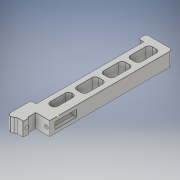
# Autodesk Inventor part: Holder
Saved by Autodesk Inventor 2019 (Build 230136000, 136)
## iProperties
Created: 2021-01-03
Part Number: Holder
Material: Generic
Document SubType Name: Modeling
Designer: Keith
Density: 1 g/cm^3
Appearance: Default
Author: Keith
## iProperties of the stored document Holder_3DPrint.ipt
Created: 2021-01-03
Part Number: Holder_3DPrint
Material: Generic
Document SubType Name: Modeling
Designer: Keith
Density: 1 g/cm^3
Appearance: Default
Author: Keith
Autodesk Inventor part; units mm, degrees
ref_plane "YZ Plane" through (0, 0, 0) normal (1, 0, 0) x (0, 1, 0)
sketch "Sketch1" plane through (0, 0, 0) normal (0, 1, 0) x (-1, 0, 0)
  line L0 (0, 0) -> (20, 0)
  line L1 (20, 0) -> (20, -100)
  line L2 (20, -100) -> (0, -100)
  line L3 (0, -100) -> (0, 0)
  line L4 (25, -100) -> (-5, -100)
  line L5 (-5, -100) -> (-5, -107.5)
  line L6 (-5, -107.5) -> (25, -107.5)
  line L7 (25, -107.5) -> (25, -100)
  line L8 (30, 0) -> (0, 0)
  line L9 (0, 0) -> (0, 7.5)
  line L10 (0, 7.5) -> (30, 7.5)
  line L11 (30, 7.5) -> (30, 0)
  line L12 (0, 7.5) -> (6, 7.5)
  line L13 (6, 7.5) -> (6, 13.5)
  line L14 (6, 13.5) -> (0, 13.5)
  line L15 (0, 13.5) -> (0, 7.5)
  dimension "d0" = 20
  dimension "d1" = 100
  dimension "d2" = 7.5
  dimension "d3" = 30
  dimension "d4" = 5
  dimension "d5" = 7.5
  dimension "d6" = 0
  dimension "d7" = 7.5
  dimension "d8" = 10
  dimension "d9" = 6
  dimension "d10" = 6
  constraints: 32 end point, 8 parallel, 4 horizontal, 4 perpendicular, 1 point on line
  measures "d0" distance of L1.end L2.end
  measures "d1" distance of L0.end L1.end
  measures "d2" distance of L6.end L4.start
  measures "d3" distance of L5.end L6.end
  measures "d4" distance between parallel lines of L7 L1
  measures "d5" distance of L8.end L9.end
  measures "d6" distance between parallel lines of L3 L9
  measures "d7" distance between parallel lines of L0 L10
  measures "d8" distance between parallel lines of L1 L11
  measures "d9" distance of L14.end L13.end
  measures "d10" distance of L13.end L12.end
extrude "Extrusion1" add sketch "Sketch1" along normal blind 13
ref_plane "Work Plane1" through (0, 6.5, 0) normal (0, 1, 0) x (1, 0, 0)
sketch "Sketch2" plane through (0, 13, 0) normal (0, 1, 0) x (1, 0, 0)
  line L0 (-25, 100) -> (-20, 100) projected
  line L1 (-20, 100) -> (-20, 0) projected
  line L2 (-20, 0) -> (-30, 0) projected
  line L3 (-30, 0) -> (-30, -7.5) projected
  line L4 (-30, -7.5) -> (-6, -7.5) projected
  line L5 (-6, -7.5) -> (-6, -13.5) projected
  line L6 (-6, -13.5) -> (0, -13.5) projected
  line L7 (0, -13.5) -> (0, 100) projected
  line L8 (0, 100) -> (5, 100) projected
  line L9 (5, 100) -> (5, 107.5) projected
  line L10 (5, 107.5) -> (-25, 107.5) projected
  line L11 (-25, 107.5) -> (-25, 100) projected
  line L12 (-30, -7.5) -> (-6, -7.5) projected
  line L13 (-30, -7.5) -> (-13, -7.5)
  line L14 (-13, -7.5) -> (-13, -20.25)
  line L15 (-13, -20.25) -> (-30, -20.25)
  line L16 (-30, -20.25) -> (-30, -7.5)
  line L17 (-13, -20.25) -> (-11.75, -20.25)
  line L18 (-11.75, -20.25) -> (-11.75, -14.75)
  line L19 (-11.75, -14.75) -> (-13, -14.75)
  line L20 (-13, -14.75) -> (-13, -20.25)
  line L21 (-13, -27.5) -> (7, -27.5)
  line L22 (7, -27.5) -> (7, -7.5)
  line L23 (7, -7.5) -> (-13, -7.5)
  line L24 (-13, -7.5) -> (-13, -27.5)
  point P0 (0, 0)
  point P1 (-3, -13.5)
  point P2 (-11.75, -17.5)
  point P3 (-13, -17.5)
  dimension "d14" = 1.25
  dimension "d15" = 5.5
  dimension "d17" = 20
  dimension "d18" = 20
  dimension "d19" = 0
  dimension "d20" = 10
  dimension "d21" = 10
  dimension "d22" = 0
  dimension "d23" = 0
  constraints: 24 end point, 6 parallel, 3 horizontal, 3 midpoint, 3 perpendicular
  measures "d14" distance of L19.end L18.end
  measures "d15" distance of L18.end L17.end
  measures "d17" distance of L23.end L22.end
  measures "d18" distance of L22.end L21.end
  measures "d19" distance between parallel lines of L4 L23
  measures "d20" distance from line of L22 point (-3, -13.5)
  measures "d21" distance from line of L4 point (-13, -17.5)
  measures "d22" vertical distance of point (-13, -17.5) point (-11.75, -17.5)
  measures "d23" distance between parallel lines of L24 L14
extrude "Extrusion2" add sketch "Sketch2" against normal up to surface (13 mm away) contours L4 L14 L15 L16 | L19 L18 L17 L14
sketch "Sketch3" plane through (0, 13, 0) normal (0, 1, 0) x (1, 0, 0)
  line L0 (-25, 100) -> (-20, 100) projected
  line L1 (-20, 100) -> (-20, 0) projected
  line L2 (-20, 0) -> (-30, 0) projected
  line L3 (-30, 0) -> (-30, -20.25) projected
  line L4 (-30, -20.25) -> (-11.75, -20.25) projected
  line L5 (-11.75, -20.25) -> (-11.75, -14.75) projected
  line L6 (-11.75, -14.75) -> (-13, -14.75) projected
  line L7 (-13, -14.75) -> (-13, -7.5) projected
  line L8 (-13, -7.5) -> (-6, -7.5) projected
  line L9 (-6, -7.5) -> (-6, -13.5) projected
  line L10 (-6, -13.5) -> (0, -13.5) projected
  line L11 (0, -13.5) -> (0, 100) projected
  line L12 (0, 100) -> (5, 100) projected
  line L13 (5, 100) -> (5, 107.5) projected
  line L14 (5, 107.5) -> (-25, 107.5) projected
  line L15 (-25, 107.5) -> (-25, 100) projected
  line L16 (-30, -20.25) -> (-11.75, -20.25) projected
  line L17 (-25, -20.25) -> (-25, 0)
  point P0 (0, 0)
  dimension "d31" = 0
  constraints: 2 end point, 1 midpoint, 1 perpendicular, 1 point on line
  measures "d31" distance between parallel lines of L15 L17
extrude "Extrusion3" cut sketch "Sketch3" against normal through all contours L17 L4 L3 L2
chamfer "Chamfer1" distance 0.5 angle 45 4 edges at (-11.75, 6.5, 14.75) (-6, 6.5, 13.5) (0, 6.5, 13.5) (-11.75, 6.5, 20.25)
fillet "Fillet1" radius 2 5 edges at (-25, 6.5, 0) (-25, 6.5, -100) (-25, 6.5, -107.5) (5, 6.5, -107.5) (5, 6.5, -100)
sketch "Sketch6" plane through (0, 13, 0) normal (0, 1, 0) x (1, 0, 0)
  arc A0 (3, 100) -> (5, 102) centre (3, 102) ccw projected
  line L0 (5, 102) -> (5, 105.5) projected
  arc A1 (5, 105.5) -> (3, 107.5) centre (3, 105.5) ccw projected
  line L1 (3, 107.5) -> (-23, 107.5) projected
  arc A2 (-23, 107.5) -> (-25, 105.5) centre (-23, 105.5) ccw projected
  line L2 (-25, 105.5) -> (-25, 102) projected
  arc A3 (-25, 102) -> (-23, 100) centre (-23, 102) ccw projected
  line L3 (-23, 100) -> (-20, 100) projected
  line L4 (-20, 100) -> (-20, 0) projected
  line L5 (-20, 0) -> (-23, 0) projected
  arc A4 (-23, 0) -> (-25, -2) centre (-23, -2) ccw projected
  line L6 (-25, -2) -> (-25, -20.25) projected
  line L7 (-25, -20.25) -> (-12.25, -20.25) projected
  line L8 (-11.75, -19.75) -> (-12.25, -20.25) projected
  line L9 (-11.75, -19.75) -> (-11.75, -15.25) projected
  line L10 (-12.25, -14.75) -> (-11.75, -15.25) projected
  line L11 (-12.25, -14.75) -> (-13, -14.75) projected
  line L12 (-13, -14.75) -> (-13, -7.5) projected
  line L13 (-13, -7.5) -> (-6, -7.5) projected
  line L14 (-6, -7.5) -> (-6, -13) projected
  line L15 (-5.5, -13.5) -> (-6, -13) projected
  line L16 (-5.5, -13.5) -> (-0.5, -13.5) projected
  line L17 (0, -13) -> (-0.5, -13.5) projected
  line L18 (0, -13) -> (0, 100) projected
  line L19 (0, 100) -> (3, 100) projected
  line L20 (-15, 5) -> (-5, 5)
  line L21 (-5, 5) -> (-5, 25)
  line L22 (-5, 25) -> (-15, 25)
  line L23 (-15, 25) -> (-15, 5)
  line L24 (-15, 30) -> (-5, 30)
  line L25 (-5, 30) -> (-5, 50)
  line L26 (-5, 50) -> (-15, 50)
  line L27 (-15, 50) -> (-15, 30)
  line L28 (-15, 55) -> (-5, 55)
  line L29 (-5, 55) -> (-5, 75)
  line L30 (-5, 75) -> (-15, 75)
  line L31 (-15, 75) -> (-15, 55)
  line L32 (-15, 80) -> (-5, 80)
  line L33 (-5, 80) -> (-5, 100)
  line L34 (-5, 100) -> (-15, 100)
  line L35 (-15, 100) -> (-15, 80)
  point P0 (0, 0)
  dimension "d45" = 5
  dimension "d46" = 20
  dimension "d47" = 20
  dimension "d48" = 20
  dimension "d49" = 20
  dimension "d50" = 5
  dimension "d51" = 5
  dimension "d52" = 5
  dimension "d53" = 10
  dimension "d54" = 5
  dimension "d55" = 5
  constraints: 32 end point, 8 parallel, 6 point on line, 4 horizontal, 4 perpendicular
  measures "d45" distance between parallel lines of L5 L20
  measures "d46" distance of L22.end L20.start
  measures "d47" distance of L26.end L24.start
  measures "d48" distance of L30.end L28.start
  measures "d49" distance of L34.end L32.start
  measures "d50" distance between parallel lines of L22 L24
  measures "d51" distance between parallel lines of L30 L32
  measures "d52" distance between parallel lines of L28 L26
  measures "d53" distance of L20.start L20.end
  measures "d54" distance between parallel lines of L4 L23
  measures "d55" distance between parallel lines of L18 L21
extrude "Extrusion5" cut sketch "Sketch6" against normal through all contours L23 L22 L21 L20 | L27 L26 L25 L24 | L31 L30 L29 L28 | L35 L34 L33 L32
sketch "Sketch7" plane through (3, 0, -107.5) normal (0, 0, -1) x (-1, 0, 0)
  line L0 (23, 13) -> (23, 0) projected
  line L1 (23, 0) -> (23, 13) projected
  line L2 (3, 0) -> (3, 13) projected
  line L3 (3, 13) -> (3, 0) projected
  circle A0 centre (22.5, 6.5) radius 2.075
  circle A1 centre (3.5, 6.5) radius 2.05
  point P0 (3, 0)
  dimension "d58" = 4.15
  dimension "d59" = 4.1
  dimension "d60" = 0.5
  dimension "d61" = 0.5
  constraints: 2 centre point
  measures "d58" diameter of A0
  measures "d59" diameter of A1
  measures "d60" distance from line of L2 A1.centre
  measures "d61" distance from line of L0 A0.centre
extrude "Extrusion6" cut sketch "Sketch7" against normal blind 110 contours A0 L0 | L0 A0
fillet "Fillet2" radius 3 16 edges at (-15, 6.5, -5) (-5, 6.5, -5) (-5, 6.5, -25) (-15, 6.5, -25) (-15, 6.5, -30) (-5, 6.5, -30) (-5, 6.5, -50) (-15, 6.5, -50) (-15, 6.5, -55) (-5, 6.5, -55) (-5, 6.5, -75) (-15, 6.5, -75) (-15, 6.5, -80) (-5, 6.5, -80) (-15, 6.5, -100) (-5, 6.5, -100)
sketch "Sketch9" plane through (0, 13, 0) normal (0, 1, 0) x (1, 0, 0)
  line L0 (-5, 72) -> (-5, 58) projected
  arc A0 (-8, 55) -> (-5, 58) centre (-8, 58) ccw projected
  line L1 (-8, 55) -> (-12, 55) projected
  arc A1 (-15, 58) -> (-12, 55) centre (-12, 58) ccw projected
  line L2 (-15, 58) -> (-15, 72) projected
  arc A2 (-12, 75) -> (-15, 72) centre (-12, 72) ccw projected
  line L3 (-12, 75) -> (-8, 75) projected
  arc A3 (-5, 72) -> (-8, 75) centre (-8, 72) ccw projected
  line L4 (-5, 22) -> (-5, 8) projected
  arc A4 (-8, 5) -> (-5, 8) centre (-8, 8) ccw projected
  line L5 (-8, 5) -> (-12, 5) projected
  arc A5 (-15, 8) -> (-12, 5) centre (-12, 8) ccw projected
  line L6 (-15, 8) -> (-15, 22) projected
  arc A6 (-12, 25) -> (-15, 22) centre (-12, 22) ccw projected
  line L7 (-12, 25) -> (-8, 25) projected
  arc A7 (-5, 22) -> (-8, 25) centre (-8, 22) ccw projected
  line L8 (-5, 47) -> (-5, 33) projected
  arc A8 (-8, 30) -> (-5, 33) centre (-8, 33) ccw projected
  line L9 (-8, 30) -> (-12, 30) projected
  arc A9 (-15, 33) -> (-12, 30) centre (-12, 33) ccw projected
  line L10 (-15, 33) -> (-15, 47) projected
  arc A10 (-12, 50) -> (-15, 47) centre (-12, 47) ccw projected
  line L11 (-12, 50) -> (-8, 50) projected
  arc A11 (-5, 47) -> (-8, 50) centre (-8, 47) ccw projected
  line L12 (-5, 97) -> (-5, 83) projected
  arc A12 (-8, 80) -> (-5, 83) centre (-8, 83) ccw projected
  line L13 (-8, 80) -> (-12, 80) projected
  arc A13 (-15, 83) -> (-12, 80) centre (-12, 83) ccw projected
  line L14 (-15, 83) -> (-15, 97) projected
  arc A14 (-12, 100) -> (-15, 97) centre (-12, 97) ccw projected
  line L15 (-12, 100) -> (-8, 100) projected
  arc A15 (-5, 97) -> (-8, 100) centre (-8, 97) ccw projected
  arc A16 (3, 100) -> (5, 102) centre (3, 102) ccw projected
  line L16 (5, 102) -> (5, 105.5) projected
  arc A17 (5, 105.5) -> (3, 107.5) centre (3, 105.5) ccw projected
  line L17 (3, 107.5) -> (-23, 107.5) projected
  arc A18 (-23, 107.5) -> (-25, 105.5) centre (-23, 105.5) ccw projected
  line L18 (-25, 105.5) -> (-25, 102) projected
  arc A19 (-25, 102) -> (-23, 100) centre (-23, 102) ccw projected
  line L19 (-23, 100) -> (-20, 100) projected
  line L20 (-20, 100) -> (-20, 0) projected
  line L21 (-20, 0) -> (-23, 0) projected
  arc A20 (-23, 0) -> (-25, -2) centre (-23, -2) ccw projected
  line L22 (-25, -2) -> (-25, -20.25) projected
  line L23 (-25, -20.25) -> (-12.25, -20.25) projected
  line L24 (-11.75, -19.75) -> (-12.25, -20.25) projected
  line L25 (-11.75, -19.75) -> (-11.75, -15.25) projected
  line L26 (-12.25, -14.75) -> (-11.75, -15.25) projected
  line L27 (-12.25, -14.75) -> (-13, -14.75) projected
  line L28 (-13, -14.75) -> (-13, -7.5) projected
  line L29 (-13, -7.5) -> (-6, -7.5) projected
  line L30 (-6, -7.5) -> (-6, -13) projected
  line L31 (-5.5, -13.5) -> (-6, -13) projected
  line L32 (-5.5, -13.5) -> (-0.5, -13.5) projected
  line L33 (0, -13) -> (-0.5, -13.5) projected
  line L34 (0, -13) -> (0, 100) projected
  line L35 (0, 100) -> (3, 100) projected
  line L36 (-25, -2) -> (-25, -20.25) projected
  line L37 (-25, -20.25) -> (-20, -20.25)
  line L38 (-20, -20.25) -> (-20, -22.25)
  line L39 (-20, -22.25) -> (-25, -22.25)
  line L40 (-25, -22.25) -> (-25, -20.25)
  point P0 (0, 0)
  dimension "d69" = 2
  constraints: 8 end point, 2 parallel, 1 horizontal, 1 perpendicular
  measures "d69" distance of L37.end L38.end
extrude "Extrusion8" add sketch "Sketch9" against normal up to surface (13 mm away) contours L23 L38 L39 L40
fillet "Fillet3" radius 3 3 edges at (-20, 6.5, 20.25) (-20, 6.5, 22.25) (-25, 6.5, 22.25)
sketch "Sketch4" plane through (-25, 13, 0) normal (-1, 0, 0) x (0, 0, 1)
  line L0 (19.25, -13) -> (2, -13) projected
  line L1 (2, 0) -> (19.25, 0) projected
  line L2 (14.75, -13) -> (14.75, 0) projected
  line L3 (20.25, 0) -> (20.25, -13) projected
  line L4 (19.25, 0) -> (19.25, -13) projected
  line L5 (2, -13) -> (2, 0) projected
  point P0 (0, -13)
  point P1 (17.25, -6.5)
  dimension "d32" = 6.5
  dimension "d33" = 2.5
  measures "d32" distance from line of L0 point (17.25, -6.5)
  measures "d33" distance from line of L2 point (17.25, -6.5)
hole "Hole1" at (-25, 6.5, 17.25) direction (1, 0, 0) diameter 3.4 end through all counterbore diameter 6.5 counterbore depth 3 clearance for "Socket Head Cap Screw" size "M3" standard "Ansi Metric M Profile"
sketch "Sketch10" plane through (0, 13, 0) normal (0, 1, 0) x (1, 0, 0)
  line L0 (-5, 72) -> (-5, 58) projected
  arc A0 (-8, 55) -> (-5, 58) centre (-8, 58) ccw projected
  line L1 (-8, 55) -> (-12, 55) projected
  arc A1 (-15, 58) -> (-12, 55) centre (-12, 58) ccw projected
  line L2 (-15, 58) -> (-15, 72) projected
  arc A2 (-12, 75) -> (-15, 72) centre (-12, 72) ccw projected
  line L3 (-12, 75) -> (-8, 75) projected
  arc A3 (-5, 72) -> (-8, 75) centre (-8, 72) ccw projected
  line L4 (-5, 22) -> (-5, 8) projected
  arc A4 (-8, 5) -> (-5, 8) centre (-8, 8) ccw projected
  line L5 (-8, 5) -> (-12, 5) projected
  arc A5 (-15, 8) -> (-12, 5) centre (-12, 8) ccw projected
  line L6 (-15, 8) -> (-15, 22) projected
  arc A6 (-12, 25) -> (-15, 22) centre (-12, 22) ccw projected
  line L7 (-12, 25) -> (-8, 25) projected
  arc A7 (-5, 22) -> (-8, 25) centre (-8, 22) ccw projected
  line L8 (-5, 47) -> (-5, 33) projected
  arc A8 (-8, 30) -> (-5, 33) centre (-8, 33) ccw projected
  line L9 (-8, 30) -> (-12, 30) projected
  arc A9 (-15, 33) -> (-12, 30) centre (-12, 33) ccw projected
  line L10 (-15, 33) -> (-15, 47) projected
  arc A10 (-12, 50) -> (-15, 47) centre (-12, 47) ccw projected
  line L11 (-12, 50) -> (-8, 50) projected
  arc A11 (-5, 47) -> (-8, 50) centre (-8, 47) ccw projected
  line L12 (-5, 97) -> (-5, 83) projected
  arc A12 (-8, 80) -> (-5, 83) centre (-8, 83) ccw projected
  line L13 (-8, 80) -> (-12, 80) projected
  arc A13 (-15, 83) -> (-12, 80) centre (-12, 83) ccw projected
  line L14 (-15, 83) -> (-15, 97) projected
  arc A14 (-12, 100) -> (-15, 97) centre (-12, 97) ccw projected
  line L15 (-12, 100) -> (-8, 100) projected
  arc A15 (-5, 97) -> (-8, 100) centre (-8, 97) ccw projected
  arc A16 (-21.6437, -22.25) -> (-19.4076, -21.25) centre (-21.6437, -19.25) ccw projected
  arc A17 (-17.1716, -20.25) -> (-19.4076, -21.25) centre (-17.1716, -23.25) ccw projected
  line L16 (-17.1716, -20.25) -> (-12.25, -20.25) projected
  line L17 (-11.75, -19.75) -> (-12.25, -20.25) projected
  line L18 (-11.75, -19.75) -> (-11.75, -15.25) projected
  line L19 (-12.25, -14.75) -> (-11.75, -15.25) projected
  line L20 (-12.25, -14.75) -> (-13, -14.75) projected
  line L21 (-13, -14.75) -> (-13, -7.5) projected
  line L22 (-13, -7.5) -> (-6, -7.5) projected
  line L23 (-6, -7.5) -> (-6, -13) projected
  line L24 (-5.5, -13.5) -> (-6, -13) projected
  line L25 (-5.5, -13.5) -> (-0.5, -13.5) projected
  line L26 (0, -13) -> (-0.5, -13.5) projected
  line L27 (0, -13) -> (0, 100) projected
  line L28 (0, 100) -> (3, 100) projected
  arc A18 (3, 100) -> (5, 102) centre (3, 102) ccw projected
  line L29 (5, 102) -> (5, 105.5) projected
  arc A19 (5, 105.5) -> (3, 107.5) centre (3, 105.5) ccw projected
  line L30 (3, 107.5) -> (-23, 107.5) projected
  arc A20 (-23, 107.5) -> (-25, 105.5) centre (-23, 105.5) ccw projected
  line L31 (-25, 105.5) -> (-25, 102) projected
  arc A21 (-25, 102) -> (-23, 100) centre (-23, 102) ccw projected
  line L32 (-23, 100) -> (-20, 100) projected
  line L33 (-20, 100) -> (-20, 0) projected
  line L34 (-20, 0) -> (-23, 0) projected
  arc A22 (-23, 0) -> (-25, -2) centre (-23, -2) ccw projected
  line L35 (-25, -2) -> (-25, -19.25) projected
  arc A23 (-25, -19.25) -> (-22, -22.25) centre (-22, -19.25) ccw projected
  line L36 (-22, -22.25) -> (-21.6437, -22.25) projected
  line L37 (0, 100) -> (5, 100)
  line L38 (5, 100) -> (5, 107.5)
  line L39 (5, 107.5) -> (0, 107.5)
  line L40 (0, 107.5) -> (0, 100)
  point P0 (0, 0)
  constraints: 8 end point, 2 parallel, 1 horizontal, 1 perpendicular
extrude "Extrusion9" cut sketch "Sketch10" against normal through all contours L30 A19 L29 A18 L28 L40 | L39 L38 A19 | A18 L38 L37
fillet "Fillet6" radius 3 1 edges at (0, 6.5, -107.5)
sketch "Sketch11" plane through (0, 13, 0) normal (0, 1, 0) x (1, 0, 0)
  line L0 (-5, 72) -> (-5, 58) projected
  arc A0 (-8, 55) -> (-5, 58) centre (-8, 58) ccw projected
  line L1 (-8, 55) -> (-12, 55) projected
  arc A1 (-15, 58) -> (-12, 55) centre (-12, 58) ccw projected
  line L2 (-15, 58) -> (-15, 72) projected
  arc A2 (-12, 75) -> (-15, 72) centre (-12, 72) ccw projected
  line L3 (-12, 75) -> (-8, 75) projected
  arc A3 (-5, 72) -> (-8, 75) centre (-8, 72) ccw projected
  line L4 (-5, 22) -> (-5, 8) projected
  arc A4 (-8, 5) -> (-5, 8) centre (-8, 8) ccw projected
  line L5 (-8, 5) -> (-12, 5) projected
  arc A5 (-15, 8) -> (-12, 5) centre (-12, 8) ccw projected
  line L6 (-15, 8) -> (-15, 22) projected
  arc A6 (-12, 25) -> (-15, 22) centre (-12, 22) ccw projected
  line L7 (-12, 25) -> (-8, 25) projected
  arc A7 (-5, 22) -> (-8, 25) centre (-8, 22) ccw projected
  line L8 (-5, 47) -> (-5, 33) projected
  arc A8 (-8, 30) -> (-5, 33) centre (-8, 33) ccw projected
  line L9 (-8, 30) -> (-12, 30) projected
  arc A9 (-15, 33) -> (-12, 30) centre (-12, 33) ccw projected
  line L10 (-15, 33) -> (-15, 47) projected
  arc A10 (-12, 50) -> (-15, 47) centre (-12, 47) ccw projected
  line L11 (-12, 50) -> (-8, 50) projected
  arc A11 (-5, 47) -> (-8, 50) centre (-8, 47) ccw projected
  line L12 (-5, 97) -> (-5, 83) projected
  arc A12 (-8, 80) -> (-5, 83) centre (-8, 83) ccw projected
  line L13 (-8, 80) -> (-12, 80) projected
  arc A13 (-15, 83) -> (-12, 80) centre (-12, 83) ccw projected
  line L14 (-15, 83) -> (-15, 97) projected
  arc A14 (-12, 100) -> (-15, 97) centre (-12, 97) ccw projected
  line L15 (-12, 100) -> (-8, 100) projected
  arc A15 (-5, 97) -> (-8, 100) centre (-8, 97) ccw projected
  arc A16 (0, 104.5) -> (-3, 107.5) centre (-3, 104.5) ccw projected
  line L16 (-3, 107.5) -> (-23, 107.5) projected
  arc A17 (-23, 107.5) -> (-25, 105.5) centre (-23, 105.5) ccw projected
  line L17 (-25, 105.5) -> (-25, 102) projected
  arc A18 (-25, 102) -> (-23, 100) centre (-23, 102) ccw projected
  line L18 (-23, 100) -> (-20, 100) projected
  line L19 (-20, 100) -> (-20, 0) projected
  line L20 (-20, 0) -> (-23, 0) projected
  arc A19 (-23, 0) -> (-25, -2) centre (-23, -2) ccw projected
  line L21 (-25, -2) -> (-25, -19.25) projected
  arc A20 (-25, -19.25) -> (-22, -22.25) centre (-22, -19.25) ccw projected
  line L22 (-22, -22.25) -> (-21.6437, -22.25) projected
  arc A21 (-21.6437, -22.25) -> (-19.4076, -21.25) centre (-21.6437, -19.25) ccw projected
  arc A22 (-17.1716, -20.25) -> (-19.4076, -21.25) centre (-17.1716, -23.25) ccw projected
  line L23 (-17.1716, -20.25) -> (-12.25, -20.25) projected
  line L24 (-11.75, -19.75) -> (-12.25, -20.25) projected
  line L25 (-11.75, -19.75) -> (-11.75, -15.25) projected
  line L26 (-12.25, -14.75) -> (-11.75, -15.25) projected
  line L27 (-12.25, -14.75) -> (-13, -14.75) projected
  line L28 (-13, -14.75) -> (-13, -7.5) projected
  line L29 (-13, -7.5) -> (-6, -7.5) projected
  line L30 (-6, -7.5) -> (-6, -13) projected
  line L31 (-5.5, -13.5) -> (-6, -13) projected
  line L32 (-5.5, -13.5) -> (-0.5, -13.5) projected
  line L33 (0, -13) -> (-0.5, -13.5) projected
  line L34 (0, -13) -> (0, 104.5) projected
  line L35 (-6, -7.5) -> (0, -7.5)
  line L36 (0, -7.5) -> (0, -13.5)
  line L37 (0, -13.5) -> (-6, -13.5)
  line L38 (-6, -13.5) -> (-6, -7.5)
  point P0 (0, 0)
  constraints: 8 end point, 2 parallel, 1 horizontal, 1 perpendicular
extrude "Extrusion10" cut sketch "Sketch11" against normal through all contours L34 L33 L32 L31 L30 L35 | L36 L37 L33 | L31 L37 L38
sketch "Sketch13" plane through (0, 0, 7.5) normal (0, 0, 1) x (1, 0, 0)
  line L0 (-13, 13) -> (-13, 0) projected
  line L1 (-13, 0) -> (0, 0) projected
  line L2 (0, 13) -> (0, 0) projected
  line L3 (-13, 13) -> (0, 13) projected
  circle A0 centre (-3, 6.5) radius 1.7
  point P0 (0, 0)
  dimension "d83" = 3
  dimension "d84" = 6.5
  dimension "d85" = 3.4
  constraints: 1 centre point, 1 coincident
  measures "d83" distance from line of L2 point (-3, 6.5)
  measures "d84" distance from line of L3 point (-3, 6.5)
  measures "d85" diameter of A0
extrude "Extrusion11" cut sketch "Sketch13" against normal blind 6 contours A0
ref_plane "Work Plane2" through (0, 0, 2.5) normal (0, 0, 1) x (1, 0, 0)
sketch "Sketch17" plane through (0, 13, 0) normal (0, 1, 0) x (1, 0, 0)
  line L0 (-13, -7.5) -> (0, -7.5) projected
  line L1 (0, -7.5) -> (0, 104.5) projected
  arc A0 (0, 104.5) -> (-3, 107.5) centre (-3, 104.5) ccw projected
  line L2 (-3, 107.5) -> (-23, 107.5) projected
  arc A1 (-23, 107.5) -> (-25, 105.5) centre (-23, 105.5) ccw projected
  line L3 (-25, 105.5) -> (-25, 102) projected
  arc A2 (-25, 102) -> (-23, 100) centre (-23, 102) ccw projected
  line L4 (-23, 100) -> (-20, 100) projected
  line L5 (-20, 100) -> (-20, 0) projected
  line L6 (-20, 0) -> (-23, 0) projected
  arc A3 (-23, 0) -> (-25, -2) centre (-23, -2) ccw projected
  line L7 (-25, -2) -> (-25, -19.25) projected
  arc A4 (-25, -19.25) -> (-22, -22.25) centre (-22, -19.25) ccw projected
  line L8 (-22, -22.25) -> (-21.6437, -22.25) projected
  arc A5 (-21.6437, -22.25) -> (-19.4076, -21.25) centre (-21.6437, -19.25) ccw projected
  arc A6 (-17.1716, -20.25) -> (-19.4076, -21.25) centre (-17.1716, -23.25) ccw projected
  line L9 (-17.1716, -20.25) -> (-12.25, -20.25) projected
  line L10 (-11.75, -19.75) -> (-12.25, -20.25) projected
  line L11 (-11.75, -19.75) -> (-11.75, -15.25) projected
  line L12 (-12.25, -14.75) -> (-11.75, -15.25) projected
  line L13 (-12.25, -14.75) -> (-13, -14.75) projected
  line L14 (-13, -14.75) -> (-13, -7.5) projected
  line L15 (-5, 97) -> (-5, 83) projected
  arc A7 (-8, 80) -> (-5, 83) centre (-8, 83) ccw projected
  line L16 (-8, 80) -> (-12, 80) projected
  arc A8 (-15, 83) -> (-12, 80) centre (-12, 83) ccw projected
  line L17 (-15, 83) -> (-15, 97) projected
  arc A9 (-12, 100) -> (-15, 97) centre (-12, 97) ccw projected
  line L18 (-12, 100) -> (-8, 100) projected
  arc A10 (-5, 97) -> (-8, 100) centre (-8, 97) ccw projected
  line L19 (-5, 47) -> (-5, 33) projected
  arc A11 (-8, 30) -> (-5, 33) centre (-8, 33) ccw projected
  line L20 (-8, 30) -> (-12, 30) projected
  arc A12 (-15, 33) -> (-12, 30) centre (-12, 33) ccw projected
  line L21 (-15, 33) -> (-15, 47) projected
  arc A13 (-12, 50) -> (-15, 47) centre (-12, 47) ccw projected
  line L22 (-12, 50) -> (-8, 50) projected
  arc A14 (-5, 47) -> (-8, 50) centre (-8, 47) ccw projected
  line L23 (-5, 22) -> (-5, 8) projected
  arc A15 (-8, 5) -> (-5, 8) centre (-8, 8) ccw projected
  line L24 (-8, 5) -> (-12, 5) projected
  arc A16 (-15, 8) -> (-12, 5) centre (-12, 8) ccw projected
  line L25 (-15, 8) -> (-15, 22) projected
  arc A17 (-12, 25) -> (-15, 22) centre (-12, 22) ccw projected
  line L26 (-12, 25) -> (-8, 25) projected
  arc A18 (-5, 22) -> (-8, 25) centre (-8, 22) ccw projected
  line L27 (-5, 72) -> (-5, 58) projected
  arc A19 (-8, 55) -> (-5, 58) centre (-8, 58) ccw projected
  line L28 (-8, 55) -> (-12, 55) projected
  arc A20 (-15, 58) -> (-12, 55) centre (-12, 58) ccw projected
  line L29 (-15, 58) -> (-15, 72) projected
  arc A21 (-12, 75) -> (-15, 72) centre (-12, 72) ccw projected
  line L30 (-12, 75) -> (-8, 75) projected
  arc A22 (-5, 72) -> (-8, 75) centre (-8, 72) ccw projected
  line L31 (-8, 5) -> (-12, 5) projected
  line L32 (-8, 5) -> (-8, 25)
  point P0 (0, 0)
  point P1 (-10, 5)
  point P2 (-10, 25)
  dimension "d101" = 3
  constraints: 2 end point, 2 midpoint, 2 point on line, 1 perpendicular
  measures "d101" distance between parallel lines of L23 L32
extrude "Extrusion15" add sketch "Sketch17" against normal up to surface (13 mm away) contours L23 A15 L32 A18
sketch "Sketch16" plane through (0, 0, 2.5) normal (0, 0, 1) x (1, 0, 0)
  circle A0 centre (-3, 6.5) radius 1.7 projected
  line L0 (-13, 13) -> (-13, 0) projected
  line L1 (-13, 0) -> (0, 0) projected
  line L2 (0, 13) -> (0, 0) projected
  line L3 (-13, 13) -> (0, 13) projected
  arc A1 (-3, 9.5) -> (-3, 3.5) centre (-3, 6.5) ccw
  line L4 (-3, 0) -> (-3, 13) projected
  line L5 (-3, 3.5) -> (0, 3.5)
  line L6 (-3, 9.5) -> (0, 9.5)
  line L7 (0, 13) -> (0, 0) projected
  line L8 (0, 3.5) -> (0, 9.5)
  dimension "d92" = 6
  constraints: 6 end point, 3 point on line, 2 point on circle, 1 centre point, 1 coincident, 1 horizontal, 1 parallel, 1 perpendicular, 1 tangent
  measures "d92" diameter of A1
extrude "Extrusion14" cut sketch "Sketch16" against normal blind 20 contours A0 L4 | A0 L4 L6 L2 L5 | L4 A0 | A0 L4 A1
fillet "Fillet9" radius 3 2 edges at (-8, 6.5, -5) (-8, 6.5, -25)
sketch "Sketch19" plane through (-22, 6.5, 17.25) normal (-1, 0, 0) x (0, 0, 1)
  circle A0 centre (0, 0) radius 3.25 projected
  circle A1 centre (0, 0) radius 1.7 projected
  point P0 (-17.25, -6.5)
extrude "Extrusion16" cut sketch "Sketch19" against normal blind 1.25
fillet "Fillet10" radius 0.5 6 edges at (-1.5, 3.5, 2.5) (-1.5, 9.5, 2.5) (-6, 6.5, 2.5) (-6, 6.5, -17.5) (-1.5, 9.5, -17.5) (-1.5, 3.5, -17.5)
chamfer "Chamfer2" distance 0.2 angle 45 22 edges at (0, 13, -48.5) (-0.8787, 13, -106.6213) (-13, 13, -107.5) (-24.4142, 13, -106.9142) (-25, 13, -103.75) (-24.4142, 13, -100.5858) (-21.5, 13, -100) (-20, 13, -50) (-21.5, 13, 0) (-24.4142, 13, 0.5858) (-25, 13, 10.625) (-24.1213, 13, 21.3713) (-21.8219, 13, 22.25) (-20.419, 13, 21.9886) (-18.3963, 13, 20.5114) (-14.7108, 13, 20.25) (-13, 13, 11.125) (-11.75, 13, 17.5) (-12, 13, 15) (-12.625, 13, 14.75) (-12, 13, 20) (-6.5, 13, 7.5)
chamfer "Chamfer3" distance 0.2 angle 45 22 edges at (0, 0, -48.5) (-0.8787, 0, -106.6213) (-13, 0, -107.5) (-24.4142, 0, -106.9142) (-25, 0, -103.75) (-24.4142, 0, -100.5858) (-21.5, 0, -100) (-20, 0, -50) (-6.5, 0, 7.5) (-13, 0, 11.125) (-12.625, 0, 14.75) (-12, 0, 15) (-11.75, 0, 17.5) (-12, 0, 20) (-14.7108, 0, 20.25) (-18.3963, 0, 20.5114) (-20.419, 0, 21.9886) (-21.8219, 0, 22.25) (-24.1213, 0, 21.3713) (-25, 0, 10.625) (-24.4142, 0, 0.5858) (-21.5, 0, 0)
fillet "Fillet11" radius 0.25 2 edges at (-20, 8.5139, -50) (-20, 4.4861, -50)
fillet "Fillet12" radius 0.25 8 edges at (0, 9.3536, -17.3536) (0, 6.5, -17.5) (0, 3.6464, -17.3536) (0, 3.5, -7.5) (0, 3.6464, 2.3536) (0, 6.5, 2.5) (0, 9.3536, 2.3536) (0, 9.5, -7.5)
fillet "Fillet13" radius 0.25 1 edges at (-17.425, 6.5, -107.5)
fillet "Fillet14" radius 0.25 4 edges at (-19.8624, 8.5431, 0) (-21.1345, 7.7783, 0) (-19.8624, 4.4569, 0) (-21.1345, 5.2217, 0)
fillet "Fillet15" radius 0.25 3 edges at (-24.8474, 5.1248, 20.1947) (-24.8474, 7.8752, 20.1947) (-25, 6.5, 14)
chamfer "Chamfer4" distance 0.2 angle 45 64 edges at (-15, 13, -15) (-14.1213, 13, -24.1213) (-11.5, 13, -25) (-8.8787, 13, -24.1213) (-8, 13, -15) (-8.8787, 13, -5.8787) (-11.5, 13, -5) (-14.1213, 13, -5.8787) (-15, 13, -40) (-14.1213, 13, -49.1213) (-10, 13, -50) (-5.8787, 13, -49.1213) (-5, 13, -40) (-5.8787, 13, -30.8787) (-10, 13, -30) (-14.1213, 13, -30.8787) (-15, 13, -65) (-14.1213, 13, -74.1213) (-10, 13, -75) (-5.8787, 13, -74.1213) (-5, 13, -65) (-5.8787, 13, -55.8787) (-10, 13, -55) (-14.1213, 13, -55.8787) (-15, 13, -90) (-14.1213, 13, -99.1213) (-10, 13, -100) (-5.8787, 13, -99.1213) (-5, 13, -90) (-5.8787, 13, -80.8787) (-10, 13, -80) (-14.1213, 13, -80.8787) (-5.8787, 0, -80.8787) (-10, 0, -80) (-14.1213, 0, -80.8787) (-15, 0, -90) (-14.1213, 0, -99.1213) (-10, 0, -100) (-5.8787, 0, -99.1213) (-5, 0, -90) (-5, 0, -65) (-5.8787, 0, -74.1213) (-10, 0, -75) (-14.1213, 0, -74.1213) (-15, 0, -65) (-14.1213, 0, -55.8787) (-10, 0, -55) (-5.8787, 0, -55.8787) (-5, 0, -40) (-5.8787, 0, -49.1213) (-10, 0, -50) (-14.1213, 0, -49.1213) (-15, 0, -40) (-14.1213, 0, -30.8787) (-10, 0, -30) (-5.8787, 0, -30.8787) (-8, 0, -15) (-8.8787, 0, -5.8787) (-11.5, 0, -5) (-14.1213, 0, -5.8787) (-15, 0, -15) (-14.1213, 0, -24.1213) (-11.5, 0, -25) (-8.8787, 0, -24.1213)
sketch "Sketch20" plane through (0, 13, 0) normal (0, 1, 0) x (1, 0, 0)
  point P0 (0, 0)
body "Solid1"
